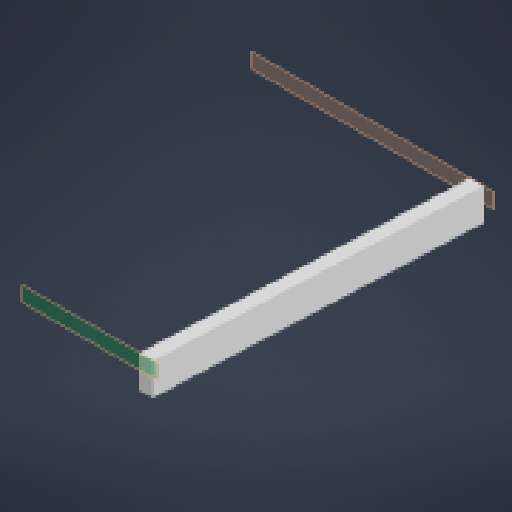
# Autodesk Inventor part: Lower Nose Diagonal
Saved by Autodesk Inventor 2027 (Build 310192000, 192)
## iProperties
Created: 2026-10-18
Part Number: Lower Nose Diagonal
Material: Generic
Document SubType Name: Modeling
Designer: lucas
Density: 1 g/cm^3
Appearance: Default
Author: lucas
Autodesk Inventor part; units mm, degrees
ref_plane "YZ Plane" through (0, 0, 0) normal (1, 0, 0) x (0, 1, 0)
ref_plane "XZ Plane" through (0, 0, 0) normal (0, 1, 0) x (-1, 0, 0)
ref_plane "XY Plane" through (0, 0, 0) normal (0, 0, 1) x (1, 0, 0)
ref_plane "Work Plane1" through (0, 0, 0) normal (0, 0, 1) x (1, 0, 0)
sketch "Sketch1" plane through (0, 0, 0) normal (0, 0, 1) x (1, 0, 0)
  line L0 (609.6, 38.1) -> (571.5, 38.1)
  line L1 (571.5, 38.1) -> (571.5, -50.8)
  line L2 (571.5, -50.8) -> (609.6, -50.8)
  line L3 (609.6, -50.8) -> (609.6, 38.1)
  point P0 (0, 0)
  dimension "d0" = 88.9
  dimension "d1" = 38.1
  constraints: 8 end point, 2 parallel, 1 horizontal, 1 perpendicular, 1 other
  measures "d0" distance of L0.end L1.end
  measures "d1" distance of L1.end L2.end
ref_plane "Work Plane2" through (342.9, -228.6, 647.7) normal (0, 0, -1) x (0, -1, 0)
sketch "Sketch2" plane through (342.9, -228.6, 647.7) normal (0, 0, -1) x (0, -1, 0)
  line L0 (-38.1, 0) -> (50.8, 0)
  line L1 (50.8, 0) -> (50.8, 38.1)
  line L2 (50.8, 38.1) -> (-38.1, 38.1)
  line L3 (-38.1, 38.1) -> (-38.1, 0)
  point P0 (-228.6, 342.9)
  dimension "d2" = 38.1
  dimension "d3" = 88.9
  constraints: 8 end point, 2 parallel, 1 horizontal, 1 perpendicular, 1 other
  measures "d2" distance of L0.end L1.end
  measures "d3" distance of L1.end L2.end
loft "Loft1" add profiles "Sketch1", "Sketch2"
body "Solid1"
